Autodesk Fusion 360 part; units mm, degrees
(part 8 of 8)
sketch "スケッチ1 (2)" plane through (0.6375, -0.1445, 2) normal (0, 0, 1) x (-1, 0, 0)
  arc A0 (-1.9084, 0.3276) -> (-1.9296, 0.1933) centre (0.6375, -0.1445) ccw
  arc A1 (-2.0377, 0.1068) -> (-1.9296, 0.1933) centre (-2.0288, 0.2064) ccw
  line L0 (-2.0377, 0.1068) -> (-2.1693, 0.1186)
  spline S0 degree 3 poles (-2.1693, 0.1186) (-2.1873, 0.1184) (-2.2236, 0.1179) (-2.278, 0.109) (-2.3326, 0.097) (-2.3875, 0.0813) (-2.4423, 0.0626) (-2.4973, 0.0409) (-2.5521, 0.0165) (-2.6069, -0.0104) (-2.6428, -0.0303) (-2.6609, -0.0403) knots 0 0 0 0 0.005388 0.010882 0.016478 0.022176 0.027974 0.033875 0.039876 0.045979 0.052183 0.052183 0.052183 0.052183
  arc A2 (-2.6609, -0.0403) -> (-2.6609, -0.2487) centre (0.6375, -0.1445) ccw
  spline S1 degree 3 poles (-2.6609, -0.2487) (-2.6428, -0.2587) (-2.6069, -0.2785) (-2.5521, -0.3054) (-2.4973, -0.3299) (-2.4423, -0.3515) (-2.3875, -0.3703) (-2.3326, -0.3859) (-2.278, -0.398) (-2.2236, -0.4068) (-2.1873, -0.4073) (-2.1693, -0.4075) knots -0.052183 -0.052183 -0.052183 -0.052183 -0.045979 -0.039876 -0.033875 -0.027974 -0.022176 -0.016478 -0.010882 -0.005388 0 0 0 0
  line L1 (-2.1693, -0.4075) -> (-2.0377, -0.3957)
  arc A3 (-1.9296, -0.4822) -> (-2.0377, -0.3957) centre (-2.0288, -0.4953) ccw
  arc A4 (-1.9296, -0.4822) -> (-1.9084, -0.6165) centre (0.6375, -0.1445) ccw
  arc A5 (-1.9844, -0.7322) -> (-1.9084, -0.6165) centre (-2.0067, -0.6347) ccw
  line L2 (-1.9844, -0.7322) -> (-2.1132, -0.7616)
  spline S2 degree 3 poles (-2.1132, -0.7616) (-2.1303, -0.7674) (-2.1647, -0.7791) (-2.2136, -0.8043) (-2.2619, -0.8326) (-2.3092, -0.8645) (-2.3556, -0.8993) (-2.4011, -0.9368) (-2.4457, -0.977) (-2.4895, -1.0195) (-2.5175, -1.0495) (-2.5317, -1.0646) knots 0 0 0 0 0.005388 0.010882 0.016478 0.022176 0.027974 0.033875 0.039876 0.045979 0.052183 0.052183 0.052183 0.052183
  arc A6 (-2.5317, -1.0646) -> (-2.4673, -1.2628) centre (0.6375, -0.1445) ccw
  spline S3 degree 3 poles (-2.4673, -1.2628) (-2.447, -1.2667) (-2.4067, -1.2745) (-2.3462, -1.2832) (-2.2865, -1.2895) (-2.2276, -1.2931) (-2.1696, -1.294) (-2.1127, -1.2919) (-2.057, -1.2865) (-2.0025, -1.2781) (-1.9678, -1.2673) (-1.9507, -1.262) knots -0.052183 -0.052183 -0.052183 -0.052183 -0.045979 -0.039876 -0.033875 -0.027974 -0.022176 -0.016478 -0.010882 -0.005388 0 0 0 0
  line L3 (-1.9507, -1.262) -> (-1.8291, -1.2101)
  arc A7 (-1.6996, -1.259) -> (-1.8291, -1.2101) centre (-1.7899, -1.302) ccw
  arc A8 (-1.6996, -1.259) -> (-1.6379, -1.3801) centre (0.6375, -0.1445) ccw
  arc A9 (-1.6745, -1.5136) -> (-1.6379, -1.3801) centre (-1.7258, -1.4278) ccw
  line L4 (-1.6745, -1.5136) -> (-1.7879, -1.5814)
  spline S4 degree 3 poles (-1.7879, -1.5814) (-1.8023, -1.5922) (-1.8314, -1.6139) (-1.8702, -1.653) (-1.9073, -1.6949) (-1.9425, -1.7398) (-1.9759, -1.7872) (-2.0076, -1.837) (-2.0376, -1.889) (-2.0661, -1.943) (-2.0835, -1.9801) (-2.0922, -1.9989) knots 0 0 0 0 0.005388 0.010882 0.016478 0.022176 0.027974 0.033875 0.039876 0.045979 0.052183 0.052183 0.052183 0.052183
  arc A10 (-2.0922, -1.9989) -> (-1.9697, -2.1675) centre (0.6375, -0.1445) ccw
  spline S5 degree 3 poles (-1.9697, -2.1675) (-1.9492, -2.165) (-1.9085, -2.1599) (-1.8483, -2.1495) (-1.7896, -2.137) (-1.7325, -2.1222) (-1.677, -2.1051) (-1.6235, -2.0856) (-1.5722, -2.0632) (-1.523, -2.0384) (-1.4933, -2.0174) (-1.4787, -2.0071) knots -0.052183 -0.052183 -0.052183 -0.052183 -0.045979 -0.039876 -0.033875 -0.027974 -0.022176 -0.016478 -0.010882 -0.005388 0 0 0 0
  line L5 (-1.4787, -2.0071) -> (-1.3791, -1.9201)
  arc A11 (-1.2408, -1.9266) -> (-1.3791, -1.9201) centre (-1.3134, -1.9955) ccw
  arc A12 (-1.2408, -1.9266) -> (-1.1447, -2.0227) centre (0.6375, -0.1445) ccw
  arc A13 (-1.1382, -2.1611) -> (-1.1447, -2.0227) centre (-1.2135, -2.0953) ccw
  line L6 (-1.1382, -2.1611) -> (-1.2251, -2.2606)
  spline S6 degree 3 poles (-1.2251, -2.2606) (-1.2355, -2.2753) (-1.2565, -2.3049) (-1.2813, -2.3541) (-1.3037, -2.4054) (-1.3232, -2.459) (-1.3403, -2.5144) (-1.3551, -2.5715) (-1.3676, -2.6302) (-1.378, -2.6904) (-1.383, -2.7311) (-1.3856, -2.7516) knots 0 0 0 0 0.005388 0.010882 0.016478 0.022176 0.027974 0.033875 0.039876 0.045979 0.052183 0.052183 0.052183 0.052183
  arc A14 (-1.3856, -2.7516) -> (-1.217, -2.8741) centre (0.6375, -0.1445) ccw
  spline S7 degree 3 poles (-1.217, -2.8741) (-1.1982, -2.8654) (-1.1611, -2.848) (-1.1071, -2.8195) (-1.0551, -2.7895) (-1.0053, -2.7578) (-0.9579, -2.7244) (-0.913, -2.6893) (-0.8711, -2.6521) (-0.832, -2.6134) (-0.8103, -2.5842) (-0.7995, -2.5698) knots -0.052183 -0.052183 -0.052183 -0.052183 -0.045979 -0.039876 -0.033875 -0.027974 -0.022176 -0.016478 -0.010882 -0.005388 0 0 0 0
  line L7 (-0.7995, -2.5698) -> (-0.7317, -2.4564)
  arc A15 (-0.5982, -2.4198) -> (-0.7317, -2.4564) centre (-0.6459, -2.5077) ccw
  arc A16 (-0.5982, -2.4198) -> (-0.4771, -2.4815) centre (0.6375, -0.1445) ccw
  arc A17 (-0.4281, -2.6111) -> (-0.4771, -2.4815) centre (-0.5201, -2.5718) ccw
  line L8 (-0.4281, -2.6111) -> (-0.4801, -2.7326)
  spline S8 degree 3 poles (-0.4801, -2.7326) (-0.4854, -2.7498) (-0.4962, -2.7844) (-0.5046, -2.8389) (-0.51, -2.8946) (-0.512, -2.9515) (-0.5112, -3.0095) (-0.5076, -3.0685) (-0.5013, -3.1282) (-0.4926, -3.1886) (-0.4848, -3.2289) (-0.4809, -3.2492) knots 0 0 0 0 0.005388 0.010882 0.016478 0.022176 0.027974 0.033875 0.039876 0.045979 0.052183 0.052183 0.052183 0.052183
  arc A18 (-0.4809, -3.2492) -> (-0.2827, -3.3136) centre (0.6375, -0.1445) ccw
  spline S9 degree 3 poles (-0.2827, -3.3136) (-0.2676, -3.2995) (-0.2376, -3.2714) (-0.1951, -3.2277) (-0.1549, -3.183) (-0.1173, -3.1375) (-0.0826, -3.0911) (-0.0507, -3.0438) (-0.0224, -2.9956) (0.0029, -2.9466) (0.0145, -2.9122) (0.0203, -2.8952) knots -0.052183 -0.052183 -0.052183 -0.052183 -0.045979 -0.039876 -0.033875 -0.027974 -0.022176 -0.016478 -0.010882 -0.005388 0 0 0 0
  line L9 (0.0203, -2.8952) -> (0.0497, -2.7663)
  arc A19 (0.1654, -2.6903) -> (0.0497, -2.7663) centre (0.1472, -2.7886) ccw
  arc A20 (0.1654, -2.6903) -> (0.2997, -2.7115) centre (0.6375, -0.1445) ccw
  arc A21 (0.3862, -2.8196) -> (0.2997, -2.7115) centre (0.2866, -2.8107) ccw
  line L10 (0.3862, -2.8196) -> (0.3744, -2.9512)
  spline S10 degree 3 poles (0.3744, -2.9512) (0.3746, -2.9692) (0.3751, -3.0056) (0.3839, -3.0599) (0.396, -3.1146) (0.4117, -3.1694) (0.4304, -3.2243) (0.452, -3.2792) (0.4765, -3.334) (0.5034, -3.3888) (0.5232, -3.4247) (0.5332, -3.4428) knots 0 0 0 0 0.005388 0.010882 0.016478 0.022176 0.027974 0.033875 0.039876 0.045979 0.052183 0.052183 0.052183 0.052183
  arc A22 (0.5332, -3.4428) -> (0.7417, -3.4428) centre (0.6375, -0.1445) ccw
  spline S11 degree 3 poles (0.7417, -3.4428) (0.7517, -3.4247) (0.7715, -3.3888) (0.7984, -3.334) (0.8229, -3.2792) (0.8445, -3.2243) (0.8632, -3.1694) (0.8789, -3.1146) (0.891, -3.0599) (0.8998, -3.0056) (0.9003, -2.9692) (0.9005, -2.9512) knots -0.052183 -0.052183 -0.052183 -0.052183 -0.045979 -0.039876 -0.033875 -0.027974 -0.022176 -0.016478 -0.010882 -0.005388 0 0 0 0
  line L11 (0.9005, -2.9512) -> (0.8887, -2.8196)
  arc A23 (0.9752, -2.7115) -> (0.8887, -2.8196) centre (0.9883, -2.8107) ccw
  arc A24 (0.9752, -2.7115) -> (1.1095, -2.6903) centre (0.6375, -0.1445) ccw
  arc A25 (1.2252, -2.7663) -> (1.1095, -2.6903) centre (1.1277, -2.7886) ccw
  line L12 (1.2252, -2.7663) -> (1.2546, -2.8952)
  spline S12 degree 3 poles (1.2546, -2.8952) (1.2604, -2.9122) (1.272, -2.9466) (1.2973, -2.9956) (1.3256, -3.0438) (1.3575, -3.0911) (1.3922, -3.1375) (1.4298, -3.183) (1.47, -3.2277) (1.5125, -3.2714) (1.5425, -3.2995) (1.5576, -3.3136) knots 0 0 0 0 0.005388 0.010882 0.016478 0.022176 0.027974 0.033875 0.039876 0.045979 0.052183 0.052183 0.052183 0.052183
  arc A26 (1.5576, -3.3136) -> (1.7558, -3.2492) centre (0.6375, -0.1445) ccw
  spline S13 degree 3 poles (1.7558, -3.2492) (1.7597, -3.2289) (1.7675, -3.1886) (1.7762, -3.1282) (1.7825, -3.0685) (1.7861, -3.0095) (1.7869, -2.9515) (1.7849, -2.8946) (1.7795, -2.8389) (1.7711, -2.7844) (1.7603, -2.7498) (1.755, -2.7326) knots -0.052183 -0.052183 -0.052183 -0.052183 -0.045979 -0.039876 -0.033875 -0.027974 -0.022176 -0.016478 -0.010882 -0.005388 0 0 0 0
  line L13 (1.755, -2.7326) -> (1.703, -2.6111)
  arc A27 (1.752, -2.4815) -> (1.703, -2.6111) centre (1.795, -2.5718) ccw
  arc A28 (1.752, -2.4815) -> (1.8731, -2.4198) centre (0.6375, -0.1445) ccw
  arc A29 (2.0066, -2.4564) -> (1.8731, -2.4198) centre (1.9208, -2.5077) ccw
  line L14 (2.0066, -2.4564) -> (2.0744, -2.5698)
  spline S14 degree 3 poles (2.0744, -2.5698) (2.0852, -2.5842) (2.1069, -2.6134) (2.146, -2.6521) (2.1879, -2.6893) (2.2328, -2.7244) (2.2802, -2.7578) (2.33, -2.7895) (2.382, -2.8195) (2.436, -2.848) (2.4731, -2.8654) (2.4919, -2.8741) knots 0 0 0 0 0.005388 0.010882 0.016478 0.022176 0.027974 0.033875 0.039876 0.045979 0.052183 0.052183 0.052183 0.052183
  arc A30 (2.4919, -2.8741) -> (2.6605, -2.7516) centre (0.6375, -0.1445) ccw
  spline S15 degree 3 poles (2.6605, -2.7516) (2.6579, -2.7311) (2.6529, -2.6904) (2.6425, -2.6302) (2.63, -2.5715) (2.6152, -2.5144) (2.5981, -2.459) (2.5786, -2.4054) (2.5562, -2.3541) (2.5314, -2.3049) (2.5104, -2.2753) (2.5, -2.2606) knots -0.052183 -0.052183 -0.052183 -0.052183 -0.045979 -0.039876 -0.033875 -0.027974 -0.022176 -0.016478 -0.010882 -0.005388 0 0 0 0
  line L15 (2.5, -2.2606) -> (2.4131, -2.1611)
  arc A31 (2.4196, -2.0227) -> (2.4131, -2.1611) centre (2.4884, -2.0953) ccw
  arc A32 (2.4196, -2.0227) -> (2.5157, -1.9266) centre (0.6375, -0.1445) ccw
  arc A33 (2.654, -1.9201) -> (2.5157, -1.9266) centre (2.5883, -1.9955) ccw
  line L16 (2.654, -1.9201) -> (2.7536, -2.0071)
  spline S16 degree 3 poles (2.7536, -2.0071) (2.7682, -2.0174) (2.7979, -2.0384) (2.8471, -2.0632) (2.8984, -2.0856) (2.9519, -2.1051) (3.0074, -2.1222) (3.0645, -2.137) (3.1232, -2.1495) (3.1834, -2.1599) (3.2241, -2.165) (3.2446, -2.1675) knots 0 0 0 0 0.005388 0.010882 0.016478 0.022176 0.027974 0.033875 0.039876 0.045979 0.052183 0.052183 0.052183 0.052183
  arc A34 (3.2446, -2.1675) -> (3.3671, -1.9989) centre (0.6375, -0.1445) ccw
  spline S17 degree 3 poles (3.3671, -1.9989) (3.3584, -1.9801) (3.341, -1.943) (3.3125, -1.889) (3.2825, -1.837) (3.2508, -1.7872) (3.2174, -1.7398) (3.1822, -1.6949) (3.1451, -1.653) (3.1063, -1.6139) (3.0772, -1.5922) (3.0628, -1.5814) knots -0.052183 -0.052183 -0.052183 -0.052183 -0.045979 -0.039876 -0.033875 -0.027974 -0.022176 -0.016478 -0.010882 -0.005388 0 0 0 0
  line L17 (3.0628, -1.5814) -> (2.9494, -1.5136)
  arc A35 (2.9128, -1.3801) -> (2.9494, -1.5136) centre (3.0007, -1.4278) ccw
  arc A36 (2.9128, -1.3801) -> (2.9745, -1.259) centre (0.6375, -0.1445) ccw
  arc A37 (3.104, -1.2101) -> (2.9745, -1.259) centre (3.0648, -1.302) ccw
  line L18 (3.104, -1.2101) -> (3.2256, -1.262)
  spline S18 degree 3 poles (3.2256, -1.262) (3.2427, -1.2673) (3.2774, -1.2781) (3.3319, -1.2865) (3.3876, -1.2919) (3.4445, -1.294) (3.5025, -1.2931) (3.5614, -1.2895) (3.6211, -1.2832) (3.6816, -1.2745) (3.7219, -1.2667) (3.7422, -1.2628) knots 0 0 0 0 0.005388 0.010882 0.016478 0.022176 0.027974 0.033875 0.039876 0.045979 0.052183 0.052183 0.052183 0.052183
  arc A38 (3.7422, -1.2628) -> (3.8066, -1.0646) centre (0.6375, -0.1445) ccw
  spline S19 degree 3 poles (3.8066, -1.0646) (3.7924, -1.0495) (3.7644, -1.0195) (3.7206, -0.977) (3.676, -0.9368) (3.6305, -0.8993) (3.5841, -0.8645) (3.5368, -0.8326) (3.4885, -0.8043) (3.4396, -0.7791) (3.4052, -0.7674) (3.3881, -0.7616) knots -0.052183 -0.052183 -0.052183 -0.052183 -0.045979 -0.039876 -0.033875 -0.027974 -0.022176 -0.016478 -0.010882 -0.005388 0 0 0 0
  line L19 (3.3881, -0.7616) -> (3.2593, -0.7322)
  arc A39 (3.1833, -0.6165) -> (3.2593, -0.7322) centre (3.2816, -0.6347) ccw
  arc A40 (3.1833, -0.6165) -> (3.2045, -0.4822) centre (0.6375, -0.1445) ccw
  arc A41 (3.3126, -0.3957) -> (3.2045, -0.4822) centre (3.3037, -0.4953) ccw
  line L20 (3.3126, -0.3957) -> (3.4442, -0.4075)
  spline S20 degree 3 poles (3.4442, -0.4075) (3.4622, -0.4073) (3.4985, -0.4068) (3.5529, -0.398) (3.6075, -0.3859) (3.6624, -0.3703) (3.7172, -0.3515) (3.7722, -0.3299) (3.827, -0.3054) (3.8818, -0.2785) (3.9177, -0.2587) (3.9358, -0.2487) knots 0 0 0 0 0.005388 0.010882 0.016478 0.022176 0.027974 0.033875 0.039876 0.045979 0.052183 0.052183 0.052183 0.052183
  arc A42 (3.9358, -0.2487) -> (3.9358, -0.0403) centre (0.6375, -0.1445) ccw
  spline S21 degree 3 poles (3.9358, -0.0403) (3.9177, -0.0303) (3.8818, -0.0104) (3.827, 0.0165) (3.7722, 0.0409) (3.7172, 0.0626) (3.6624, 0.0813) (3.6075, 0.097) (3.5529, 0.109) (3.4985, 0.1179) (3.4622, 0.1184) (3.4442, 0.1186) knots -0.052183 -0.052183 -0.052183 -0.052183 -0.045979 -0.039876 -0.033875 -0.027974 -0.022176 -0.016478 -0.010882 -0.005388 0 0 0 0
  line L21 (3.4442, 0.1186) -> (3.3126, 0.1068)
  arc A43 (3.2045, 0.1933) -> (3.3126, 0.1068) centre (3.3037, 0.2064) ccw
  arc A44 (3.2045, 0.1933) -> (3.1833, 0.3276) centre (0.6375, -0.1445) ccw
  arc A45 (3.2593, 0.4433) -> (3.1833, 0.3276) centre (3.2816, 0.3458) ccw
  line L22 (3.2593, 0.4433) -> (3.3881, 0.4727)
  spline S22 degree 3 poles (3.3881, 0.4727) (3.4052, 0.4785) (3.4396, 0.4901) (3.4885, 0.5154) (3.5368, 0.5437) (3.5841, 0.5755) (3.6305, 0.6103) (3.676, 0.6479) (3.7206, 0.6881) (3.7644, 0.7306) (3.7924, 0.7606) (3.8066, 0.7757) knots 0 0 0 0 0.005388 0.010882 0.016478 0.022176 0.027974 0.033875 0.039876 0.045979 0.052183 0.052183 0.052183 0.052183
  arc A46 (3.8066, 0.7757) -> (3.7422, 0.9739) centre (0.6375, -0.1445) ccw
  spline S23 degree 3 poles (3.7422, 0.9739) (3.7219, 0.9778) (3.6816, 0.9856) (3.6211, 0.9943) (3.5614, 1.0005) (3.5025, 1.0042) (3.4445, 1.005) (3.3876, 1.003) (3.3319, 0.9975) (3.2774, 0.9892) (3.2427, 0.9784) (3.2256, 0.973) knots -0.052183 -0.052183 -0.052183 -0.052183 -0.045979 -0.039876 -0.033875 -0.027974 -0.022176 -0.016478 -0.010882 -0.005388 0 0 0 0
  line L23 (3.2256, 0.973) -> (3.104, 0.9211)
  arc A47 (2.9745, 0.97) -> (3.104, 0.9211) centre (3.0648, 1.0131) ccw
  arc A48 (2.9745, 0.97) -> (2.9128, 1.0912) centre (0.6375, -0.1445) ccw
  arc A49 (2.9494, 1.2247) -> (2.9128, 1.0912) centre (3.0007, 1.1389) ccw
  line L24 (2.9494, 1.2247) -> (3.0628, 1.2925)
  spline S24 degree 3 poles (3.0628, 1.2925) (3.0772, 1.3033) (3.1063, 1.325) (3.1451, 1.3641) (3.1822, 1.4059) (3.2174, 1.4509) (3.2508, 1.4983) (3.2825, 1.5481) (3.3125, 1.6001) (3.341, 1.6541) (3.3584, 1.6912) (3.3671, 1.7099) knots 0 0 0 0 0.005388 0.010882 0.016478 0.022176 0.027974 0.033875 0.039876 0.045979 0.052183 0.052183 0.052183 0.052183
  arc A50 (3.3671, 1.7099) -> (3.2446, 1.8786) centre (0.6375, -0.1445) ccw
  spline S25 degree 3 poles (3.2446, 1.8786) (3.2241, 1.876) (3.1834, 1.871) (3.1232, 1.8605) (3.0645, 1.8481) (3.0074, 1.8333) (2.9519, 1.8162) (2.8984, 1.7967) (2.8471, 1.7743) (2.7979, 1.7495) (2.7682, 1.7285) (2.7536, 1.7181) knots -0.052183 -0.052183 -0.052183 -0.052183 -0.045979 -0.039876 -0.033875 -0.027974 -0.022176 -0.016478 -0.010882 -0.005388 0 0 0 0
  line L25 (2.7536, 1.7181) -> (2.654, 1.6312)
  arc A51 (2.5157, 1.6377) -> (2.654, 1.6312) centre (2.5883, 1.7065) ccw
  arc A52 (2.5157, 1.6377) -> (2.4196, 1.7338) centre (0.6375, -0.1445) ccw
  arc A53 (2.4131, 1.8721) -> (2.4196, 1.7338) centre (2.4884, 1.8063) ccw
  line L26 (2.4131, 1.8721) -> (2.5, 1.9717)
  spline S26 degree 3 poles (2.5, 1.9717) (2.5104, 1.9863) (2.5314, 2.016) (2.5562, 2.0652) (2.5786, 2.1164) (2.5981, 2.17) (2.6152, 2.2254) (2.63, 2.2826) (2.6425, 2.3413) (2.6529, 2.4015) (2.6579, 2.4422) (2.6605, 2.4627) knots 0 0 0 0 0.005388 0.010882 0.016478 0.022176 0.027974 0.033875 0.039876 0.045979 0.052183 0.052183 0.052183 0.052183
  arc A54 (2.6605, 2.4627) -> (2.4919, 2.5852) centre (0.6375, -0.1445) ccw
  spline S27 degree 3 poles (2.4919, 2.5852) (2.4731, 2.5764) (2.436, 2.559) (2.382, 2.5305) (2.33, 2.5005) (2.2802, 2.4688) (2.2328, 2.4354) (2.1879, 2.4003) (2.146, 2.3632) (2.1069, 2.3244) (2.0852, 2.2953) (2.0744, 2.2809) knots -0.052183 -0.052183 -0.052183 -0.052183 -0.045979 -0.039876 -0.033875 -0.027974 -0.022176 -0.016478 -0.010882 -0.005388 0 0 0 0
  line L27 (2.0744, 2.2809) -> (2.0066, 2.1674)
  arc A55 (1.8731, 2.1309) -> (2.0066, 2.1674) centre (1.9208, 2.2188) ccw
  arc A56 (1.8731, 2.1309) -> (1.752, 2.1926) centre (0.6375, -0.1445) ccw
  arc A57 (1.703, 2.3221) -> (1.752, 2.1926) centre (1.795, 2.2828) ccw
  line L28 (1.703, 2.3221) -> (1.755, 2.4437)
  spline S28 degree 3 poles (1.755, 2.4437) (1.7603, 2.4608) (1.7711, 2.4955) (1.7795, 2.5499) (1.7849, 2.6056) (1.7869, 2.6626) (1.7861, 2.7206) (1.7825, 2.7795) (1.7762, 2.8392) (1.7675, 2.8997) (1.7597, 2.9399) (1.7558, 2.9602) knots 0 0 0 0 0.005388 0.010882 0.016478 0.022176 0.027974 0.033875 0.039876 0.045979 0.052183 0.052183 0.052183 0.052183
  arc A58 (1.7558, 2.9602) -> (1.5576, 3.0247) centre (0.6375, -0.1445) ccw
  spline S29 degree 3 poles (1.5576, 3.0247) (1.5425, 3.0105) (1.5125, 2.9825) (1.47, 2.9387) (1.4298, 2.8941) (1.3922, 2.8486) (1.3575, 2.8022) (1.3256, 2.7549) (1.2973, 2.7066) (1.272, 2.6577) (1.2604, 2.6233) (1.2546, 2.6062) knots -0.052183 -0.052183 -0.052183 -0.052183 -0.045979 -0.039876 -0.033875 -0.027974 -0.022176 -0.016478 -0.010882 -0.005388 0 0 0 0
  line L29 (1.2546, 2.6062) -> (1.2252, 2.4774)
  arc A59 (1.1095, 2.4013) -> (1.2252, 2.4774) centre (1.1277, 2.4997) ccw
  arc A60 (1.1095, 2.4013) -> (0.9752, 2.4226) centre (0.6375, -0.1445) ccw
  arc A61 (0.8887, 2.5307) -> (0.9752, 2.4226) centre (0.9883, 2.5217) ccw
  line L30 (0.8887, 2.5307) -> (0.9005, 2.6623)
  spline S30 degree 3 poles (0.9005, 2.6623) (0.9003, 2.6803) (0.8998, 2.7166) (0.891, 2.771) (0.8789, 2.8256) (0.8632, 2.8804) (0.8445, 2.9353) (0.8229, 2.9902) (0.7984, 3.0451) (0.7715, 3.0999) (0.7517, 3.1358) (0.7417, 3.1539) knots 0 0 0 0 0.005388 0.010882 0.016478 0.022176 0.027974 0.033875 0.039876 0.045979 0.052183 0.052183 0.052183 0.052183
  arc A62 (0.7417, 3.1539) -> (0.5332, 3.1539) centre (0.6375, -0.1445) ccw
  spline S31 degree 3 poles (0.5332, 3.1539) (0.5232, 3.1358) (0.5034, 3.0999) (0.4765, 3.0451) (0.452, 2.9902) (0.4304, 2.9353) (0.4117, 2.8804) (0.396, 2.8256) (0.3839, 2.771) (0.3751, 2.7166) (0.3746, 2.6803) (0.3744, 2.6623) knots -0.052183 -0.052183 -0.052183 -0.052183 -0.045979 -0.039876 -0.033875 -0.027974 -0.022176 -0.016478 -0.010882 -0.005388 0 0 0 0
  line L31 (0.3744, 2.6623) -> (0.3862, 2.5307)
  arc A63 (0.2997, 2.4226) -> (0.3862, 2.5307) centre (0.2866, 2.5217) ccw
  arc A64 (0.2997, 2.4226) -> (0.1654, 2.4013) centre (0.6375, -0.1445) ccw
  arc A65 (0.0497, 2.4774) -> (0.1654, 2.4013) centre (0.1472, 2.4997) ccw
  line L32 (0.0497, 2.4774) -> (0.0203, 2.6062)
  spline S32 degree 3 poles (0.0203, 2.6062) (0.0145, 2.6233) (0.0029, 2.6577) (-0.0224, 2.7066) (-0.0507, 2.7549) (-0.0826, 2.8022) (-0.1173, 2.8486) (-0.1549, 2.8941) (-0.1951, 2.9387) (-0.2376, 2.9825) (-0.2676, 3.0105) (-0.2827, 3.0247) knots 0 0 0 0 0.005388 0.010882 0.016478 0.022176 0.027974 0.033875 0.039876 0.045979 0.052183 0.052183 0.052183 0.052183
  arc A66 (-0.2827, 3.0247) -> (-0.4809, 2.9602) centre (0.6375, -0.1445) ccw
  spline S33 degree 3 poles (-0.4809, 2.9602) (-0.4848, 2.9399) (-0.4926, 2.8997) (-0.5013, 2.8392) (-0.5076, 2.7795) (-0.5112, 2.7206) (-0.512, 2.6626) (-0.51, 2.6056) (-0.5046, 2.5499) (-0.4962, 2.4955) (-0.4854, 2.4608) (-0.4801, 2.4437) knots -0.052183 -0.052183 -0.052183 -0.052183 -0.045979 -0.039876 -0.033875 -0.027974 -0.022176 -0.016478 -0.010882 -0.005388 0 0 0 0
  line L33 (-0.4801, 2.4437) -> (-0.4281, 2.3221)
  arc A67 (-0.4771, 2.1926) -> (-0.4281, 2.3221) centre (-0.5201, 2.2828) ccw
  arc A68 (-0.4771, 2.1926) -> (-0.5982, 2.1309) centre (0.6375, -0.1445) ccw
  arc A69 (-0.7317, 2.1674) -> (-0.5982, 2.1309) centre (-0.6459, 2.2188) ccw
  line L34 (-0.7317, 2.1674) -> (-0.7995, 2.2809)
  spline S34 degree 3 poles (-0.7995, 2.2809) (-0.8103, 2.2953) (-0.832, 2.3244) (-0.8711, 2.3632) (-0.913, 2.4003) (-0.9579, 2.4354) (-1.0053, 2.4688) (-1.0551, 2.5005) (-1.1071, 2.5305) (-1.1611, 2.559) (-1.1982, 2.5764) (-1.217, 2.5852) knots 0 0 0 0 0.005388 0.010882 0.016478 0.022176 0.027974 0.033875 0.039876 0.045979 0.052183 0.052183 0.052183 0.052183
  arc A70 (-1.217, 2.5852) -> (-1.3856, 2.4627) centre (0.6375, -0.1445) ccw
  spline S35 degree 3 poles (-1.3856, 2.4627) (-1.383, 2.4422) (-1.378, 2.4015) (-1.3676, 2.3413) (-1.3551, 2.2826) (-1.3403, 2.2254) (-1.3232, 2.17) (-1.3037, 2.1164) (-1.2813, 2.0652) (-1.2565, 2.016) (-1.2355, 1.9863) (-1.2251, 1.9717) knots -0.052183 -0.052183 -0.052183 -0.052183 -0.045979 -0.039876 -0.033875 -0.027974 -0.022176 -0.016478 -0.010882 -0.005388 0 0 0 0
  line L35 (-1.2251, 1.9717) -> (-1.1382, 1.8721)
  arc A71 (-1.1447, 1.7338) -> (-1.1382, 1.8721) centre (-1.2135, 1.8063) ccw
  arc A72 (-1.1447, 1.7338) -> (-1.2408, 1.6377) centre (0.6375, -0.1445) ccw
  arc A73 (-1.3791, 1.6312) -> (-1.2408, 1.6377) centre (-1.3134, 1.7065) ccw
  line L36 (-1.3791, 1.6312) -> (-1.4787, 1.7181)
  spline S36 degree 3 poles (-1.4787, 1.7181) (-1.4933, 1.7285) (-1.523, 1.7495) (-1.5722, 1.7743) (-1.6235, 1.7967) (-1.677, 1.8162) (-1.7325, 1.8333) (-1.7896, 1.8481) (-1.8483, 1.8605) (-1.9085, 1.871) (-1.9492, 1.876) (-1.9697, 1.8786) knots 0 0 0 0 0.005388 0.010882 0.016478 0.022176 0.027974 0.033875 0.039876 0.045979 0.052183 0.052183 0.052183 0.052183
  arc A74 (-1.9697, 1.8786) -> (-2.0922, 1.7099) centre (0.6375, -0.1445) ccw
  spline S37 degree 3 poles (-2.0922, 1.7099) (-2.0835, 1.6912) (-2.0661, 1.6541) (-2.0376, 1.6001) (-2.0076, 1.5481) (-1.9759, 1.4983) (-1.9425, 1.4509) (-1.9073, 1.4059) (-1.8702, 1.3641) (-1.8314, 1.325) (-1.8023, 1.3033) (-1.7879, 1.2925) knots -0.052183 -0.052183 -0.052183 -0.052183 -0.045979 -0.039876 -0.033875 -0.027974 -0.022176 -0.016478 -0.010882 -0.005388 0 0 0 0
  line L37 (-1.7879, 1.2925) -> (-1.6745, 1.2247)
  arc A75 (-1.6379, 1.0912) -> (-1.6745, 1.2247) centre (-1.7258, 1.1389) ccw
  arc A76 (-1.6379, 1.0912) -> (-1.6996, 0.97) centre (0.6375, -0.1445) ccw
  arc A77 (-1.8291, 0.9211) -> (-1.6996, 0.97) centre (-1.7899, 1.0131) ccw
  line L38 (-1.8291, 0.9211) -> (-1.9507, 0.973)
  spline S38 degree 3 poles (-1.9507, 0.973) (-1.9678, 0.9784) (-2.0025, 0.9892) (-2.057, 0.9975) (-2.1127, 1.003) (-2.1696, 1.005) (-2.2276, 1.0042) (-2.2865, 1.0005) (-2.3462, 0.9943) (-2.4067, 0.9856) (-2.447, 0.9778) (-2.4673, 0.9739) knots 0 0 0 0 0.005388 0.010882 0.016478 0.022176 0.027974 0.033875 0.039876 0.045979 0.052183 0.052183 0.052183 0.052183
  arc A78 (-2.4673, 0.9739) -> (-2.5317, 0.7757) centre (0.6375, -0.1445) ccw
  spline S39 degree 3 poles (-2.5317, 0.7757) (-2.5175, 0.7606) (-2.4895, 0.7306) (-2.4457, 0.6881) (-2.4011, 0.6479) (-2.3556, 0.6103) (-2.3092, 0.5755) (-2.2619, 0.5437) (-2.2136, 0.5154) (-2.1647, 0.4901) (-2.1303, 0.4785) (-2.1132, 0.4727) knots -0.052183 -0.052183 -0.052183 -0.052183 -0.045979 -0.039876 -0.033875 -0.027974 -0.022176 -0.016478 -0.010882 -0.005388 0 0 0 0
  line L39 (-2.1132, 0.4727) -> (-1.9844, 0.4433)
  arc A79 (-1.9084, 0.3276) -> (-1.9844, 0.4433) centre (-2.0067, 0.3458) ccw
  circle A80 centre (0.6375, -0.1445) radius 0.75
  circle A81 centre (0.6375, -0.1445) radius 0.5
  dimension "d9" = 1
  constraint concentric A0 A81
  measures "d9" diameter of A81
extrude "押し出し3" add sketch "スケッチ1 (2)" against normal blind 2 contours A80 in component "Spur Gear (20 teeth)"
component "歯車M0.3T20 v1" placed x (1, 0, 0) y (0, 1, 0) z (0, 0, 1) at (0, 0, 0)
component "Spur Gear (20 teeth)" placed x (1, 0, 0) y (0, 1, 0) z (0, 0, 1) at (0, 0, 0) in component "歯車M0.3T20 v1"

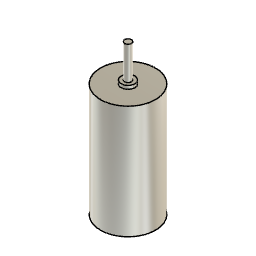
design "NFP-D0816S"
Autodesk Fusion 360 part; units mm, degrees
sketch "スケッチ1" plane through (0, 0, 0) normal (0, 0, 1) x (1, 0, 0)
  circle A0 centre (0, 0) radius 4.05
  dimension "d1" = 8.1
  constraint coincident A0.centre origin
  measures "d1" diameter of A0
extrude "押し出し1" add sketch "スケッチ1" along normal blind 16.7
sketch "スケッチ2" plane through (0, 0, 16.7) normal (0, 0, 1) x (-1, 0, 0)
  circle A0 centre (0, 0) radius 4.05
  circle A1 centre (0, 0) radius 1
  dimension "d4" = 2
  constraint coincident A0.centre A1.centre
  measures "d4" diameter of A1
extrude "押し出し2" add sketch "スケッチ2" along normal blind 0.5 contours A1
sketch "スケッチ3" plane through (0, 0, 17.2) normal (0, 0, 1) x (-1, 0, 0)
  circle A0 centre (0, 0) radius 1
  circle A1 centre (0, 0) radius 0.5
  dimension "d7" = 1
  constraint concentric A0 A1
  measures "d7" diameter of A1
extrude "押し出し3" add sketch "スケッチ3" along normal blind 4.9 contours A1

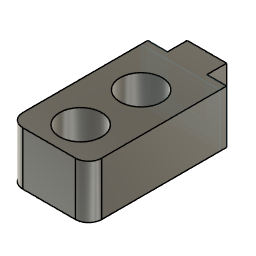
design "センサホルダ"
Autodesk Fusion 360 part; units mm, degrees
sketch "スケッチ1" plane through (0, 0, 0) normal (0, 0, 1) x (1, 0, 0)
  line L0 (0, 0) -> (-6, 0)
  line L1 (-6, 0) -> (-6, 10)
  line L2 (-6, 10) -> (0, 10)
  line L3 (0, 10) -> (0, 0)
  dimension "d1" = 6
  dimension "d2" = 10
  constraint horizontal L0
  constraint vertical L1
  constraint horizontal L2
  constraint vertical L3
  constraint coincident L0.start L3.end
  measures "d1" distance of L0.start L0.end
  measures "d2" distance of L0.start L2.end
extrude "押し出し1" add sketch "スケッチ1" along normal blind 4
sketch "スケッチ2" plane through (0, 0, 0) normal (0, 0, -1) x (1, 0, 0)
  line L0 (-6, -10) -> (0, -10)
  line L1 (0, -10) -> (0, 0)
  line L2 (0, 0) -> (-6, 0)
  line L3 (-6, 0) -> (-6, -10)
  line L4 (0, -10) -> (-3, -10)
  line L5 (-3, -10) -> (-3, -7)
  circle A0 centre (-3, -7) radius 1.6
  line L6 (-3, -7) -> (-3, -4)
  line L7 (-3, -5.4) -> (-3, -2.4)
  circle A1 centre (-3, -2.4) radius 1.6
  dimension "d7" = 3
  dimension "d8" = 3
  dimension "d9" = 3.2
  dimension "d10" = 3.2
  constraint coincident L0.end L1.start
  constraint midpoint L0 L4.end
  constraint perpendicular L4 L5
  constraint coincident L5.end A0.centre
  constraint parallel L5 L6
  constraint coincident A0 L7.start
  constraint coincident L6 L7.start
  constraint parallel L6 L7
  constraint coincident L7.end A1.centre
  constraint coincident L6.end A1
  measures "d7" distance of L4.end L5.end
  measures "d8" distance of L7.start L7.end
  measures "d9" diameter of A0
  measures "d10" diameter of A1
extrude "押し出し2" cut sketch "スケッチ2" against normal blind 8.5 contours L5 A0 L6 | L5 A0 L6 | A1
fillet "フィレット1" radius 1 2 edges at (-6, 0, 2) (0, 0, 2)
sketch "スケッチ3" plane through (0, 10, 0) normal (0, 1, 0) x (-1, 0, 0)
  line L0 (0, 0) -> (6, 0)
  line L1 (6, 0) -> (6, 4)
  line L2 (6, 4) -> (0, 4)
  line L3 (0, 4) -> (0, 0)
sketch "スケッチ4" plane through (0, 10, 0) normal (0, 1, 0) x (-1, 0, 0)
  line L0 (3, 2) -> (3, 4)
  line L1 (3, 4) -> (0, 4)
  line L2 (0, 4) -> (0, -1)
  line L3 (0, -1) -> (3, -1)
  line L4 (6, -1) -> (3, -1)
  line L5 (6, 4) -> (6, -1)
  line L6 (3, 4) -> (6, 4)
  line L7 (4, 4) -> (0, 4)
  line L8 (0, 4) -> (2, 4)
  line L9 (6, 0) -> (0, 0)
  line L10 (0, 0) -> (0, 4)
  line L11 (0, 4) -> (6, 4)
  line L12 (6, 4) -> (6, 0)
  line L13 (6, 4) -> (3, 4)
  dimension "d27" = 5
  dimension "d28" = 3
  constraint vertical L0
  constraint horizontal L1
  constraint vertical L2
  constraint horizontal L3
  constraint symmetric L1.start L0 L6.start
  constraint symmetric L0 L1.end L5.start
  constraint symmetric L0 L2.end L4.start
  constraint symmetric L0 L3.end L4.end
  constraint horizontal L7
  constraint midpoint L7 L8.end
  constraint horizontal L9
  constraint vertical L10
  constraint horizontal L11
  constraint vertical L12
  constraint midpoint L11 L0.end
  measures "d27" distance of L1.end L2.end
  measures "d28" distance of L2.end L3.end
extrude "押し出し3" add sketch "スケッチ4" along normal blind 0.5
sketch "スケッチ5" plane through (0, 10.5, 0) normal (0, 1, 0) x (-1, 0, 0)
  line L0 (0, 4) -> (0, -1)
  line L1 (0, -1) -> (6, -1)
  line L2 (6, -1) -> (6, 4)
  line L3 (6, 4) -> (0, 4)
  line L4 (6, 0.5) -> (0, 0.5)
  line L5 (3, 0.5) -> (3, 4)
  line L6 (3, 4) -> (1.5, 4)
  line L7 (1.5, 4) -> (1.5, 1)
  line L8 (1.5, 1) -> (3, 1)
  line L9 (3, 1) -> (3, 4)
  line L10 (4.5, 1) -> (3, 1)
  line L11 (4.5, 4) -> (4.5, 1)
  line L12 (3, 4) -> (4.5, 4)
  dimension "d17" = 1.5
  dimension "d18" = 3
  constraint coincident L2 L4.start
  constraint coincident L0 L4.end
  constraint perpendicular L0 L4
  constraint midpoint L4 L5.start
  constraint midpoint L3 L5.end
  constraint horizontal L6
  constraint vertical L7
  constraint horizontal L8
  constraint vertical L9
  constraint symmetric L5.end L9 L6.start
  constraint symmetric L6.end L9 L11.start
  constraint symmetric L7.end L9 L10.start
  constraint symmetric L8.end L9 L10.end
  measures "d17" distance of L5.end L6.end
  measures "d18" distance of L6 L8
extrude "押し出し4" add sketch "スケッチ5" along normal blind 1.5 contours L3 L5 L6 L7 L8 L9 | L3 L5 L9 L10 L11 L12
sketch "スケッチ6" plane through (0, 10, 0) normal (0, -1, 0) x (1, 0, 0)
  line L0 (-6, 0) -> (-6, -1)
  line L1 (-6, -1) -> (0, -1)
  line L2 (0, -1) -> (0, 0)
  line L3 (0, 0) -> (-6, 0)
  line L4 (-6, 0.0393) -> (0, 0.0393)
  line L5 (0, 0.0393) -> (0, -1)
  line L6 (0, -1) -> (-6, -1)
  line L7 (-6, -1) -> (-6, 0.0393)
  constraint horizontal L4
  constraint vertical L5
  constraint horizontal L6
  constraint vertical L7
  constraint coincident L1.end L2.start
  constraint coincident L0 L4.start
extrude "押し出し5" cut sketch "スケッチ6" against normal blind 1.2 contours L0 L1 L2 L3 L5 L6 L7
sketch "スケッチ7" plane through (0, 10.5, 0) normal (0, 1, 0) x (-1, 0, 0)
  line L0 (0, 0) -> (6, 0)
  line L1 (6, 0) -> (6, 4)
  line L2 (6, 4) -> (4.5, 4)
  line L3 (4.5, 4) -> (4.5, 1)
  line L4 (4.5, 1) -> (1.5, 1)
  line L5 (1.5, 1) -> (1.5, 4)
  line L6 (1.5, 4) -> (0, 4)
  line L7 (0, 4) -> (0, 0)
extrude "押し出し6" add 1 faces at (-3.0399, 9.8652, 0) along direction (0, 0, -1) blind 0.039
equation "d9 = 3 mm + 0.2 mm"

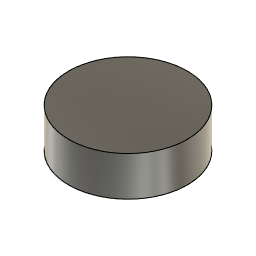
design "3mm磁石"
Autodesk Fusion 360 part; units mm, degrees
sketch "スケッチ1" plane through (0, 0, 0) normal (0, 0, 1) x (1, 0, 0)
  circle A0 centre (0, 0) radius 1.5
  dimension "d1" = 3
  constraint coincident A0.centre origin
  measures "d1" diameter of A0
extrude "押し出し1" add sketch "スケッチ1" along normal blind 1

design "バッテリー4s_300mAh"
Autodesk Fusion 360 part; units mm, degrees
sketch "スケッチ1" plane through (0, 0, 0) normal (0, 0, 1) x (1, 0, 0)
  line L0 (0, 0) -> (-56, 0)
  line L1 (-56, 0) -> (-56, 23)
  line L2 (-56, 23) -> (0, 23)
  line L3 (0, 23) -> (0, 0)
  dimension "d1" = 56
  dimension "d2" = 23
  constraint horizontal L0
  constraint vertical L1
  constraint horizontal L2
  constraint vertical L3
  constraint coincident L0.start L3.end
  measures "d1" distance of L0.start L0.end
  measures "d2" distance of L0.start L2.end
extrude "押し出し1" add sketch "スケッチ1" along normal blind 17.5

design "エンコーダ基板"
Autodesk Fusion 360 part; units mm, degrees
sketch "スケッチ1" plane through (0, 0, 0) normal (0, 0, 1) x (1, 0, 0)
  line L0 (-60, 0) -> (80, 0) construction
  line L1 (0, 50) -> (0, -45) construction
  line L2 (-35, 4.15) -> (40, 4.15)
  line L3 (-4, 0) -> (-4, 27)
  line L4 (4, 0) -> (4, 27)
  line L5 (-4, 0) -> (4, 0)
  line L6 (-7, 6.65) -> (8.5487, 6.65) construction
  line L7 (-7, 1.65) -> (12, 1.65) construction
  line L8 (-3.2, -1.7136) -> (-3.2, 11.747) construction
  line L9 (3.2, -1.7136) -> (3.2, 11.747) construction
  line L10 (-7, 7.15) -> (8.2247, 7.15)
  dimension "d1" = 4.15
  dimension "d3" = 4
  dimension "d4" = 2.5
  dimension "d5" = 2.5
  dimension "d6" = 3.2
  dimension "d7" = 3
  constraint horizontal L0
  constraint perpendicular L0 L1
  constraint horizontal L2
  constraint coincident L0 L3.start
  constraint perpendicular L0 L3
  constraint symmetric L1 L3.start L4.start
  constraint symmetric L1 L3.end L4.end
  constraint perpendicular L4 L6
  constraint perpendicular L1 L7
  constraint perpendicular L6 L8
  constraint symmetric L1 L8.start L9.start
  constraint symmetric L1 L8.end L9.end
  constraint horizontal L10
  measures "d1" distance of L0 L2
  measures "d3" distance of L1 L3
  measures "d4" distance of L2 L6
  measures "d5" distance of L2 L7
  measures "d6" distance of L1 L8
  measures "d7" distance of L2 L10
extrude "押し出し1" add sketch "スケッチ1" along normal blind 0.6
sketch "スケッチ3" plane through (0, 0, 0) normal (0, 0, 1) x (1, 0, 0)
  line L0 (-35, 4.15) -> (40, 4.15)
  line L1 (0, 50) -> (0, -45) construction
  line L2 (-7, 1.65) -> (12, 1.65) construction
  line L3 (-3.2, -1.7136) -> (-3.2, 11.747) construction
  line L4 (-7, 6.65) -> (8.5487, 6.65) construction
  line L5 (3.2, -1.7136) -> (3.2, 11.747) construction
  dimension "d10" = 2.5
  dimension "d11" = 2.5
  dimension "d12" = 3.2
  constraint horizontal L0
  constraint perpendicular L1 L2
  constraint perpendicular L3 L4
  constraint symmetric L5.start L3.start L1
  constraint symmetric L5.end L3.end L1
  measures "d10" distance of L0 L4
  measures "d11" distance of L0 L2
  measures "d12" distance of L1 L3

design "スパーギアＭ0,3_T71"
description: Spur Gear; Module: 0.3; Num Teeth: 71; Pressure Angle: 20.0; Backlash: 0.00 mm
Autodesk Fusion 360 part; units mm, degrees
sketch "スケッチ1" plane through (0, 0, 0) normal (0, 0, 1) x (1, 0, 0) in component "Spur Gear (71 teeth)"
  circle A0 centre (0, 0) radius 10.2392
  circle A1 centre (0, 0) radius 4
extrude "押し出し1" add sketch "スケッチ1" along normal blind 2 in component "Spur Gear (71 teeth)"
sketch "スケッチ2" plane through (0, 0, 0) normal (0, 0, 1) x (1, 0, 0) in component "Spur Gear (71 teeth)"
  spline S0 degree 5 poles (10.0009, -0.3705) (10.0036, -0.3705) (10.009, -0.3704) (10.0172, -0.3703) (10.028, -0.37) (10.0416, -0.3695) (10.0552, -0.3687) (10.0688, -0.3678) (10.0824, -0.3666) (10.0959, -0.3653) (10.1095, -0.3639) (10.1231, -0.3623) (10.1367, -0.3606) (10.1503, -0.3588) (10.1639, -0.3568) (10.1775, -0.3548) (10.1911, -0.3527) (10.2047, -0.3505) (10.2183, -0.3482) (10.2319, -0.3458) (10.2455, -0.3433) (10.2591, -0.3407) (10.2727, -0.338) (10.2863, -0.3352) (10.2999, -0.3324) (10.3135, -0.3295) (10.3271, -0.3265) (10.3407, -0.3234) (10.3543, -0.3203) (10.3679, -0.317) (10.3815, -0.3137) (10.3951, -0.3104) (10.4086, -0.3069) (10.4222, -0.3034) (10.4358, -0.2998) (10.4494, -0.2962) (10.463, -0.2925) (10.4765, -0.2887) (10.4901, -0.2848) (10.5037, -0.2809) (10.5172, -0.277) (10.5308, -0.2729) (10.5444, -0.2688) (10.5579, -0.2646) (10.5715, -0.2604) (10.585, -0.2561) (10.5986, -0.2518) (10.6121, -0.2474) (10.6256, -0.2429) (10.6392, -0.2384) (10.6527, -0.2338) (10.6662, -0.2292) (10.6798, -0.2245) (10.6933, -0.2197) (10.7068, -0.2149) (10.7203, -0.21) (10.7338, -0.2051) (10.7473, -0.2001) (10.7608, -0.1951) (10.7743, -0.19) (10.7878, -0.1849) (10.8013, -0.1797) (10.8148, -0.1744) (10.8283, -0.1691) (10.8417, -0.1638) (10.8552, -0.1584) (10.8687, -0.1529) (10.8821, -0.1474) (10.8956, -0.1418) (10.909, -0.1362) (10.9225, -0.1306) (10.9332, -0.126) (10.9413, -0.1225) (10.9467, -0.1202) (10.9494, -0.1191) knots 0 0 0 0 0 0 0.01428571 0.02857143 0.04285714 0.05714286 0.07142857 0.08571429 0.1 0.11428571 0.12857143 0.14285714 0.15714286 0.17142857 0.18571429 0.2 0.21428571 0.22857143 0.24285714 0.25714286 0.27142857 0.28571429 0.3 0.31428571 0.32857143 0.34285714 0.35714286 0.37142857 0.38571429 0.4 0.41428571 0.42857143 0.44285714 0.45714286 0.47142857 0.48571429 0.5 0.51428571 0.52857143 0.54285714 0.55714286 0.57142857 0.58571429 0.6 0.61428571 0.62857143 0.64285714 0.65714286 0.67142857 0.68571429 0.7 0.71428571 0.72857143 0.74285714 0.75714286 0.77142857 0.78571429 0.8 0.81428571 0.82857143 0.84285714 0.85714286 0.87142857 0.88571429 0.9 0.91428571 0.92857143 0.94285714 0.95714286 0.97142857 0.98571429 1 1 1 1 1 1
  spline S1 degree 5 poles (10.0009, 0.3705) (10.0036, 0.3705) (10.009, 0.3704) (10.0172, 0.3703) (10.028, 0.37) (10.0416, 0.3695) (10.0552, 0.3687) (10.0688, 0.3678) (10.0824, 0.3666) (10.0959, 0.3653) (10.1095, 0.3639) (10.1231, 0.3623) (10.1367, 0.3606) (10.1503, 0.3588) (10.1639, 0.3568) (10.1775, 0.3548) (10.1911, 0.3527) (10.2047, 0.3505) (10.2183, 0.3482) (10.2319, 0.3458) (10.2455, 0.3433) (10.2591, 0.3407) (10.2727, 0.338) (10.2863, 0.3352) (10.2999, 0.3324) (10.3135, 0.3295) (10.3271, 0.3265) (10.3407, 0.3234) (10.3543, 0.3203) (10.3679, 0.317) (10.3815, 0.3137) (10.3951, 0.3104) (10.4086, 0.3069) (10.4222, 0.3034) (10.4358, 0.2998) (10.4494, 0.2962) (10.463, 0.2925) (10.4765, 0.2887) (10.4901, 0.2848) (10.5037, 0.2809) (10.5172, 0.277) (10.5308, 0.2729) (10.5444, 0.2688) (10.5579, 0.2646) (10.5715, 0.2604) (10.585, 0.2561) (10.5986, 0.2518) (10.6121, 0.2474) (10.6256, 0.2429) (10.6392, 0.2384) (10.6527, 0.2338) (10.6662, 0.2292) (10.6798, 0.2245) (10.6933, 0.2197) (10.7068, 0.2149) (10.7203, 0.21) (10.7338, 0.2051) (10.7473, 0.2001) (10.7608, 0.1951) (10.7743, 0.19) (10.7878, 0.1849) (10.8013, 0.1797) (10.8148, 0.1744) (10.8283, 0.1691) (10.8417, 0.1638) (10.8552, 0.1584) (10.8687, 0.1529) (10.8821, 0.1474) (10.8956, 0.1418) (10.909, 0.1362) (10.9225, 0.1306) (10.9332, 0.126) (10.9413, 0.1225) (10.9467, 0.1202) (10.9494, 0.1191) knots 0 0 0 0 0 0 0.01428571 0.02857143 0.04285714 0.05714286 0.07142857 0.08571429 0.1 0.11428571 0.12857143 0.14285714 0.15714286 0.17142857 0.18571429 0.2 0.21428571 0.22857143 0.24285714 0.25714286 0.27142857 0.28571429 0.3 0.31428571 0.32857143 0.34285714 0.35714286 0.37142857 0.38571429 0.4 0.41428571 0.42857143 0.44285714 0.45714286 0.47142857 0.48571429 0.5 0.51428571 0.52857143 0.54285714 0.55714286 0.57142857 0.58571429 0.6 0.61428571 0.62857143 0.64285714 0.65714286 0.67142857 0.68571429 0.7 0.71428571 0.72857143 0.74285714 0.75714286 0.77142857 0.78571429 0.8 0.81428571 0.82857143 0.84285714 0.85714286 0.87142857 0.88571429 0.9 0.91428571 0.92857143 0.94285714 0.95714286 0.97142857 0.98571429 1 1 1 1 1 1
  arc A0 (10.9494, -0.1191) -> (10.9494, 0.1191) centre (0, 0) ccw
  line L0 (10.0009, 0.3705) -> (10.0009, -0.3705)
  point P0 (10.0683, -0.3678)
  point P1 (10.1359, -0.3606)
  point P2 (10.2036, -0.3506)
  point P3 (10.2714, -0.3382)
  point P4 (10.3392, -0.3237)
  point P5 (10.407, -0.3073)
  point P6 (10.4749, -0.2891)
  point P7 (10.5427, -0.2693)
  point P8 (10.6106, -0.2479)
  point P9 (10.6784, -0.2249)
  point P10 (10.7462, -0.2005)
  point P11 (10.814, -0.1747)
  point P12 (10.8817, -0.1476)
  point P13 (10.0683, 0.3678)
  point P14 (10.1359, 0.3606)
  point P15 (10.2036, 0.3506)
  point P16 (10.2714, 0.3382)
  point P17 (10.3392, 0.3237)
  point P18 (10.407, 0.3073)
  point P19 (10.4749, 0.2891)
  point P20 (10.5427, 0.2693)
  point P21 (10.6106, 0.2479)
  point P22 (10.6784, 0.2249)
  point P23 (10.7462, 0.2005)
  point P24 (10.814, 0.1747)
  point P25 (10.8817, 0.1476)
extrude "押し出し2" add sketch "スケッチ2" along normal blind 2 in component "Spur Gear (71 teeth)"
fillet "フィレット1" radius 0.1 2 edges at (10.2334, 0.3455, 1) (10.2334, -0.3455, 1) in component "Spur Gear (71 teeth)"
pattern_circular "C パターン1" count 71 over 360 about axis through (0, 0, 0) along (0, 0, 1) of "押し出し2", "フィレット1" in component "Spur Gear (71 teeth)"
sketch "スケッチ3" plane through (0, 0, 0) normal (0, 0, 1) x (1, 0, 0) in component "Spur Gear (71 teeth)"
  circle A0 centre (0, 0) radius 10.65 construction
component "Spur Gear (71 teeth)" placed x (1, 0, 0) y (0, 1, 0) z (0, 0, 1) at (0, 0, 0)

design "M3*5mmスペーサー"
Autodesk Fusion 360 part; units mm, degrees
sketch "スケッチ1" plane through (0, 0, 0) normal (0, 0, 1) x (1, 0, 0)
  circle A0 centre (0, 0) radius 1.5
  circle A1 centre (0, 0) radius 3
  dimension "d1" = 3
  dimension "d2" = 6
  constraint coincident A0.centre A1.centre
  constraint concentric A0 A1
  measures "d1" diameter of A0
  measures "d2" diameter of A1
extrude "押し出し1" add sketch "スケッチ1" along normal blind 5
